Autodesk Fusion 360 part; units mm, degrees
(part 18 of 28)
  line L1257 (50.9078, 31.8439) -> (50.9969, 31.6692)
  line L1258 (50.9969, 31.6692) -> (51.0575, 31.4826)
  line L1259 (51.0575, 31.4826) -> (51.0882, 31.2889)
  line L1260 (51.0882, 31.2889) -> (51.092, 31.1908)
  line L1261 (51.092, 31.1908) -> (51.092, 30.6908)
  line L1262 (51.092, 30.6908) -> (51.0882, 30.5927)
  line L1263 (51.0882, 30.5927) -> (51.0575, 30.399)
  line L1264 (51.0575, 30.399) -> (50.9969, 30.2125)
  line L1265 (50.9969, 30.2125) -> (50.9078, 30.0377)
  line L1266 (50.9078, 30.0377) -> (50.7925, 29.879)
  line L1267 (50.7925, 29.879) -> (50.6538, 29.7403)
  line L1268 (50.6538, 29.7403) -> (50.4952, 29.625)
  line L1269 (50.4952, 29.625) -> (50.3204, 29.536)
  line L1270 (50.3204, 29.536) -> (50.1338, 29.4754)
  line L1271 (50.1338, 29.4754) -> (49.9401, 29.4447)
  line L1272 (49.9401, 29.4447) -> (49.744, 29.4447)
  line L1273 (49.744, 29.4447) -> (49.5502, 29.4754)
  line L1274 (49.5502, 29.4754) -> (49.3637, 29.536)
  line L1275 (49.3637, 29.536) -> (49.1889, 29.625)
  line L1276 (49.1889, 29.625) -> (49.0302, 29.7403)
  line L1277 (49.0302, 29.7403) -> (48.8915, 29.879)
  line L1278 (48.8915, 29.879) -> (48.7762, 30.0377)
  line L1279 (48.7762, 30.0377) -> (48.6872, 30.2125)
  line L1280 (48.6872, 30.2125) -> (48.6266, 30.399)
  line L1281 (48.6266, 30.399) -> (48.5959, 30.5927)
  line L1282 (48.5959, 30.5927) -> (48.592, 30.6908)
  line L1283 (48.592, 30.6908) -> (48.592, 31.1908)
  line L1284 (48.592, 31.1908) -> (48.5959, 31.2889)
  line L1285 (48.5959, 31.2889) -> (48.6266, 31.4826)
  line L1286 (48.6266, 31.4826) -> (48.6872, 31.6692)
  line L1287 (48.6872, 31.6692) -> (48.7762, 31.8439)
  line L1288 (48.7762, 31.8439) -> (48.8915, 32.0026)
  line L1289 (48.8915, 32.0026) -> (49.0302, 32.1413)
  line L1290 (49.0302, 32.1413) -> (49.1889, 32.2566)
  line L1291 (49.1889, 32.2566) -> (49.3637, 32.3457)
  line L1292 (49.3637, 32.3457) -> (49.5502, 32.4063)
  line L1293 (49.5502, 32.4063) -> (49.744, 32.437)
  line L1294 (49.744, 32.437) -> (49.9401, 32.437)
  line L1295 (49.9401, 32.437) -> (50.1338, 32.4063)
  line L1296 (111.0938, 32.4063) -> (111.2804, 32.3457)
  line L1297 (111.2804, 32.3457) -> (111.4552, 32.2566)
  line L1298 (111.4552, 32.2566) -> (111.6138, 32.1413)
  line L1299 (111.6138, 32.1413) -> (111.7525, 32.0026)
  line L1300 (111.7525, 32.0026) -> (111.8678, 31.8439)
  line L1301 (111.8678, 31.8439) -> (111.9569, 31.6692)
  line L1302 (111.9569, 31.6692) -> (112.0175, 31.4826)
  line L1303 (112.0175, 31.4826) -> (112.0482, 31.2889)
  line L1304 (112.0482, 31.2889) -> (112.052, 31.1908)
  line L1305 (112.052, 31.1908) -> (112.052, 30.6908)
  line L1306 (112.052, 30.6908) -> (112.0482, 30.5927)
  line L1307 (112.0482, 30.5927) -> (112.0175, 30.399)
  line L1308 (112.0175, 30.399) -> (111.9569, 30.2125)
  line L1309 (111.9569, 30.2125) -> (111.8678, 30.0377)
  line L1310 (111.8678, 30.0377) -> (111.7525, 29.879)
  line L1311 (111.7525, 29.879) -> (111.6138, 29.7403)
  line L1312 (111.6138, 29.7403) -> (111.4552, 29.625)
  line L1313 (111.4552, 29.625) -> (111.2804, 29.536)
  line L1314 (111.2804, 29.536) -> (111.0938, 29.4754)
  line L1315 (111.0938, 29.4754) -> (110.9001, 29.4447)
  line L1316 (110.9001, 29.4447) -> (110.704, 29.4447)
  line L1317 (110.704, 29.4447) -> (110.5102, 29.4754)
  line L1318 (110.5102, 29.4754) -> (110.3237, 29.536)
  line L1319 (110.3237, 29.536) -> (110.1489, 29.625)
  line L1320 (110.1489, 29.625) -> (109.9902, 29.7403)
  line L1321 (109.9902, 29.7403) -> (109.8515, 29.879)
  line L1322 (109.8515, 29.879) -> (109.7362, 30.0377)
  line L1323 (109.7362, 30.0377) -> (109.6472, 30.2125)
  line L1324 (109.6472, 30.2125) -> (109.5866, 30.399)
  line L1325 (109.5866, 30.399) -> (109.5559, 30.5927)
  line L1326 (109.5559, 30.5927) -> (109.552, 30.6908)
  line L1327 (109.552, 30.6908) -> (109.552, 31.1908)
  line L1328 (109.552, 31.1908) -> (109.5559, 31.2889)
  line L1329 (109.5559, 31.2889) -> (109.5866, 31.4826)
  line L1330 (109.5866, 31.4826) -> (109.6472, 31.6692)
  line L1331 (109.6472, 31.6692) -> (109.7362, 31.8439)
  line L1332 (109.7362, 31.8439) -> (109.8515, 32.0026)
  line L1333 (109.8515, 32.0026) -> (109.9902, 32.1413)
  line L1334 (109.9902, 32.1413) -> (110.1489, 32.2566)
  line L1335 (110.1489, 32.2566) -> (110.3237, 32.3457)
  line L1336 (110.3237, 32.3457) -> (110.5102, 32.4063)
  line L1337 (110.5102, 32.4063) -> (110.704, 32.437)
  line L1338 (110.704, 32.437) -> (110.9001, 32.437)
  line L1339 (110.9001, 32.437) -> (111.0938, 32.4063)
  line L1340 (23.2295, 32.6644) -> (23.3427, 32.6091)
  line L1341 (23.3427, 32.6091) -> (23.4319, 32.5199)
  line L1342 (23.4319, 32.5199) -> (23.4872, 32.4067)
  line L1343 (23.4872, 32.4067) -> (23.5031, 32.2975)
  line L1344 (23.5031, 32.2975) -> (23.5031, 30.6131)
  line L1345 (23.5031, 30.6131) -> (23.4872, 30.5039)
  line L1346 (23.4872, 30.5039) -> (23.4319, 30.3907)
  line L1347 (23.4319, 30.3907) -> (23.3427, 30.3016)
  line L1348 (23.3427, 30.3016) -> (23.2295, 30.2462)
  line L1349 (23.2295, 30.2462) -> (23.1203, 30.2303)
  line L1350 (23.1203, 30.2303) -> (20.8859, 30.2303)
  line L1351 (20.8859, 30.2303) -> (20.7767, 30.2462)
  line L1352 (20.7767, 30.2462) -> (20.6635, 30.3016)
  line L1353 (20.6635, 30.3016) -> (20.5744, 30.3907)
  line L1354 (20.5744, 30.3907) -> (20.519, 30.5039)
  line L1355 (20.519, 30.5039) -> (20.5031, 30.6131)
  line L1356 (20.5031, 30.6131) -> (20.5031, 32.2975)
  line L1357 (20.5031, 32.2975) -> (20.519, 32.4067)
  line L1358 (20.519, 32.4067) -> (20.5744, 32.5199)
  line L1359 (20.5744, 32.5199) -> (20.6635, 32.6091)
  line L1360 (20.6635, 32.6091) -> (20.7767, 32.6644)
  line L1361 (20.7767, 32.6644) -> (20.8859, 32.6803)
  line L1362 (20.8859, 32.6803) -> (23.1203, 32.6803)
  line L1363 (23.1203, 32.6803) -> (23.2295, 32.6644)
  line L1364 (84.1895, 32.6644) -> (84.3027, 32.6091)
  line L1365 (84.3027, 32.6091) -> (84.3919, 32.5199)
  line L1366 (84.3919, 32.5199) -> (84.4472, 32.4067)
  line L1367 (84.4472, 32.4067) -> (84.4631, 32.2975)
  line L1368 (84.4631, 32.2975) -> (84.4631, 30.6131)
  line L1369 (84.4631, 30.6131) -> (84.4472, 30.5039)
  line L1370 (84.4472, 30.5039) -> (84.3919, 30.3907)
  line L1371 (84.3919, 30.3907) -> (84.3027, 30.3016)
  line L1372 (84.3027, 30.3016) -> (84.1895, 30.2462)
  line L1373 (84.1895, 30.2462) -> (84.0803, 30.2303)
  line L1374 (84.0803, 30.2303) -> (81.8459, 30.2303)
  line L1375 (81.8459, 30.2303) -> (81.7367, 30.2462)
  line L1376 (81.7367, 30.2462) -> (81.6235, 30.3016)
  line L1377 (81.6235, 30.3016) -> (81.5344, 30.3907)
  line L1378 (81.5344, 30.3907) -> (81.479, 30.5039)
  line L1379 (81.479, 30.5039) -> (81.4631, 30.6131)
  line L1380 (81.4631, 30.6131) -> (81.4631, 32.2975)
  line L1381 (81.4631, 32.2975) -> (81.479, 32.4067)
  line L1382 (81.479, 32.4067) -> (81.5344, 32.5199)
  line L1383 (81.5344, 32.5199) -> (81.6235, 32.6091)
  line L1384 (81.6235, 32.6091) -> (81.7367, 32.6644)
  line L1385 (81.7367, 32.6644) -> (81.8459, 32.6803)
  line L1386 (81.8459, 32.6803) -> (84.0803, 32.6803)
  line L1387 (84.0803, 32.6803) -> (84.1895, 32.6644)
  line L1388 (10.9199, 32.7804) -> (11.1098, 32.7504)
  line L1389 (11.1098, 32.7504) -> (11.2926, 32.691)
  line L1390 (11.2926, 32.691) -> (11.4639, 32.6037)
  line L1391 (11.4639, 32.6037) -> (11.6194, 32.4907)
  line L1392 (11.6194, 32.4907) -> (11.7553, 32.3548)
  line L1393 (11.7553, 32.3548) -> (11.8683, 32.1993)
  line L1394 (11.8683, 32.1993) -> (11.9556, 32.028)
  line L1395 (11.9556, 32.028) -> (12.015, 31.8452)
  line L1396 (12.015, 31.8452) -> (12.0451, 31.6553)
  line L1397 (12.0451, 31.6553) -> (12.0451, 31.4631)
  line L1398 (12.0451, 31.4631) -> (12.015, 31.2732)
  line L1399 (12.015, 31.2732) -> (11.9556, 31.0904)
  line L1400 (11.9556, 31.0904) -> (11.8683, 30.9191)
  line L1401 (11.8683, 30.9191) -> (11.7553, 30.7636)
  line L1402 (11.7553, 30.7636) -> (11.6194, 30.6277)
  line L1403 (11.6194, 30.6277) -> (11.4639, 30.5147)
  line L1404 (11.4639, 30.5147) -> (11.2926, 30.4274)
  line L1405 (11.2926, 30.4274) -> (11.1098, 30.368)
  line L1406 (11.1098, 30.368) -> (10.9199, 30.338)
  line L1407 (10.9199, 30.338) -> (10.8238, 30.3342)
  line L1408 (10.8238, 30.3342) -> (10.2738, 30.3342)
  line L1409 (10.2738, 30.3342) -> (10.1777, 30.338)
  line L1410 (10.1777, 30.338) -> (9.9879, 30.368)
  line L1411 (9.9879, 30.368) -> (9.8051, 30.4274)
  line L1412 (9.8051, 30.4274) -> (9.6338, 30.5147)
  line L1413 (9.6338, 30.5147) -> (9.4783, 30.6277)
  line L1414 (9.4783, 30.6277) -> (9.3423, 30.7636)
  line L1415 (9.3423, 30.7636) -> (9.2294, 30.9191)
  line L1416 (9.2294, 30.9191) -> (9.1421, 31.0904)
  line L1417 (9.1421, 31.0904) -> (9.0827, 31.2732)
  line L1418 (9.0827, 31.2732) -> (9.0526, 31.4631)
  line L1419 (9.0526, 31.4631) -> (9.0526, 31.6553)
  line L1420 (9.0526, 31.6553) -> (9.0827, 31.8452)
  line L1421 (9.0827, 31.8452) -> (9.1421, 32.028)
  line L1422 (9.1421, 32.028) -> (9.2294, 32.1993)
  line L1423 (9.2294, 32.1993) -> (9.3423, 32.3548)
  line L1424 (9.3423, 32.3548) -> (9.4783, 32.4907)
  line L1425 (9.4783, 32.4907) -> (9.6338, 32.6037)
  line L1426 (9.6338, 32.6037) -> (9.8051, 32.691)
  line L1427 (9.8051, 32.691) -> (9.9879, 32.7504)
  line L1428 (9.9879, 32.7504) -> (10.1777, 32.7804)
  line L1429 (10.1777, 32.7804) -> (10.2738, 32.7842)
  line L1430 (10.2738, 32.7842) -> (10.8238, 32.7842)
  line L1431 (10.8238, 32.7842) -> (10.9199, 32.7804)
  line L1432 (71.8799, 32.7804) -> (72.0698, 32.7504)
  line L1433 (72.0698, 32.7504) -> (72.2526, 32.691)
  line L1434 (72.2526, 32.691) -> (72.4239, 32.6037)
  line L1435 (72.4239, 32.6037) -> (72.5794, 32.4907)
  line L1436 (72.5794, 32.4907) -> (72.7153, 32.3548)
  line L1437 (72.7153, 32.3548) -> (72.8283, 32.1993)
  line L1438 (72.8283, 32.1993) -> (72.9156, 32.028)
  line L1439 (72.9156, 32.028) -> (72.975, 31.8452)
  line L1440 (72.975, 31.8452) -> (73.0051, 31.6553)
  line L1441 (73.0051, 31.6553) -> (73.0051, 31.4631)
  line L1442 (73.0051, 31.4631) -> (72.975, 31.2732)
  line L1443 (72.975, 31.2732) -> (72.9156, 31.0904)
  line L1444 (72.9156, 31.0904) -> (72.8283, 30.9191)
  line L1445 (72.8283, 30.9191) -> (72.7153, 30.7636)
  line L1446 (72.7153, 30.7636) -> (72.5794, 30.6277)
  line L1447 (72.5794, 30.6277) -> (72.4239, 30.5147)
  line L1448 (72.4239, 30.5147) -> (72.2526, 30.4274)
  line L1449 (72.2526, 30.4274) -> (72.0698, 30.368)
  line L1450 (72.0698, 30.368) -> (71.8799, 30.338)
  line L1451 (71.8799, 30.338) -> (71.7838, 30.3342)
  line L1452 (71.7838, 30.3342) -> (71.2338, 30.3342)
  line L1453 (71.2338, 30.3342) -> (71.1377, 30.338)
  line L1454 (71.1377, 30.338) -> (70.9479, 30.368)
  line L1455 (70.9479, 30.368) -> (70.7651, 30.4274)
  line L1456 (70.7651, 30.4274) -> (70.5938, 30.5147)
  line L1457 (70.5938, 30.5147) -> (70.4383, 30.6277)
  line L1458 (70.4383, 30.6277) -> (70.3023, 30.7636)
  line L1459 (70.3023, 30.7636) -> (70.1894, 30.9191)
  line L1460 (70.1894, 30.9191) -> (70.1021, 31.0904)
  line L1461 (70.1021, 31.0904) -> (70.0427, 31.2732)
  line L1462 (70.0427, 31.2732) -> (70.0126, 31.4631)
  line L1463 (70.0126, 31.4631) -> (70.0126, 31.6553)
  line L1464 (70.0126, 31.6553) -> (70.0427, 31.8452)
  line L1465 (70.0427, 31.8452) -> (70.1021, 32.028)
  line L1466 (70.1021, 32.028) -> (70.1894, 32.1993)
  line L1467 (70.1894, 32.1993) -> (70.3023, 32.3548)
  line L1468 (70.3023, 32.3548) -> (70.4383, 32.4907)
  line L1469 (70.4383, 32.4907) -> (70.5938, 32.6037)
  line L1470 (70.5938, 32.6037) -> (70.7651, 32.691)
  line L1471 (70.7651, 32.691) -> (70.9479, 32.7504)
  line L1472 (70.9479, 32.7504) -> (71.1377, 32.7804)
  line L1473 (71.1377, 32.7804) -> (71.2338, 32.7842)
  line L1474 (71.2338, 32.7842) -> (71.7838, 32.7842)
  line L1475 (71.7838, 32.7842) -> (71.8799, 32.7804)
  line L1476 (44.7485, 30.6785) -> (41.5485, 30.6785)
  line L1477 (41.5485, 30.6785) -> (41.5485, 32.6785)
  line L1478 (41.5485, 32.6785) -> (44.7485, 32.6785)
  line L1479 (44.7485, 32.6785) -> (44.7485, 30.6785)
  line L1480 (105.7085, 30.6785) -> (102.5085, 30.6785)
  line L1481 (102.5085, 30.6785) -> (102.5085, 32.6785)
  line L1482 (102.5085, 32.6785) -> (105.7085, 32.6785)
  line L1483 (105.7085, 32.6785) -> (105.7085, 30.6785)
  line L1484 (17.2908, 40.7988) -> (14.8408, 40.7988)
  line L1485 (14.8408, 40.7988) -> (14.8408, 43.7988)
  line L1486 (14.8408, 43.7988) -> (17.2908, 43.7988)
  line L1487 (17.2908, 43.7988) -> (17.2908, 40.7988)
  line L1488 (52.2158, 40.7988) -> (49.7658, 40.7988)
  line L1489 (49.7658, 40.7988) -> (49.7658, 43.7988)
  line L1490 (49.7658, 43.7988) -> (52.2158, 43.7988)
  line L1491 (52.2158, 43.7988) -> (52.2158, 40.7988)
  line L1492 (87.1408, 40.7988) -> (84.6908, 40.7988)
  line L1493 (84.6908, 40.7988) -> (84.6908, 43.7988)
  line L1494 (84.6908, 43.7988) -> (87.1408, 43.7988)
  line L1495 (87.1408, 43.7988) -> (87.1408, 40.7988)
  line L1496 (122.0658, 40.7988) -> (119.6158, 40.7988)
  line L1497 (119.6158, 40.7988) -> (119.6158, 43.7988)
  line L1498 (119.6158, 43.7988) -> (122.0658, 43.7988)
  line L1499 (122.0658, 43.7988) -> (122.0658, 40.7988)
  line L1500 (13.8118, 43.765) -> (13.9946, 43.7056)
  line L1501 (13.9946, 43.7056) -> (14.1659, 43.6183)
  line L1502 (14.1659, 43.6183) -> (14.3214, 43.5053)
  line L1503 (14.3214, 43.5053) -> (14.4573, 43.3694)
  line L1504 (14.4573, 43.3694) -> (14.5703, 43.2139)
  line L1505 (14.5703, 43.2139) -> (14.6576, 43.0426)
  line L1506 (14.6576, 43.0426) -> (14.717, 42.8598)
  line L1507 (14.717, 42.8598) -> (14.747, 42.6699)
  line L1508 (14.747, 42.6699) -> (14.7508, 42.5738)
  line L1509 (14.7508, 42.5738) -> (14.7508, 42.0238)
  line L1510 (14.7508, 42.0238) -> (14.747, 41.9277)
  line L1511 (14.747, 41.9277) -> (14.717, 41.7379)
  line L1512 (14.717, 41.7379) -> (14.6576, 41.555)
  line L1513 (14.6576, 41.555) -> (14.5703, 41.3838)
  line L1514 (14.5703, 41.3838) -> (14.4573, 41.2283)
  line L1515 (14.4573, 41.2283) -> (14.3214, 41.0923)
  line L1516 (14.3214, 41.0923) -> (14.1659, 40.9794)
  line L1517 (14.1659, 40.9794) -> (13.9946, 40.8921)
  line L1518 (13.9946, 40.8921) -> (13.8118, 40.8327)
  line L1519 (13.8118, 40.8327) -> (13.6219, 40.8026)
  line L1520 (13.6219, 40.8026) -> (13.4297, 40.8026)
  line L1521 (13.4297, 40.8026) -> (13.2398, 40.8327)
  line L1522 (13.2398, 40.8327) -> (13.057, 40.8921)
  line L1523 (13.057, 40.8921) -> (12.8857, 40.9794)
  line L1524 (12.8857, 40.9794) -> (12.7302, 41.0923)
  line L1525 (12.7302, 41.0923) -> (12.5943, 41.2283)
  line L1526 (12.5943, 41.2283) -> (12.4813, 41.3838)
  line L1527 (12.4813, 41.3838) -> (12.394, 41.5551)
  line L1528 (12.394, 41.5551) -> (12.3346, 41.7379)
  line L1529 (12.3346, 41.7379) -> (12.3046, 41.9277)
  line L1530 (12.3046, 41.9277) -> (12.3008, 42.0238)
  line L1531 (12.3008, 42.0238) -> (12.3008, 42.5738)
  line L1532 (12.3008, 42.5738) -> (12.3046, 42.6699)
  line L1533 (12.3046, 42.6699) -> (12.3346, 42.8598)
  line L1534 (12.3346, 42.8598) -> (12.394, 43.0426)
  line L1535 (12.394, 43.0426) -> (12.4813, 43.2139)
  line L1536 (12.4813, 43.2139) -> (12.5943, 43.3694)
  line L1537 (12.5943, 43.3694) -> (12.7302, 43.5053)
  line L1538 (12.7302, 43.5053) -> (12.8857, 43.6183)
  line L1539 (12.8857, 43.6183) -> (13.057, 43.7056)
  line L1540 (13.057, 43.7056) -> (13.2398, 43.765)
  line L1541 (13.2398, 43.765) -> (13.4297, 43.7951)
  line L1542 (13.4297, 43.7951) -> (13.6219, 43.7951)
  line L1543 (13.6219, 43.7951) -> (13.8118, 43.765)
  line L1544 (48.7368, 43.765) -> (48.9196, 43.7056)
  line L1545 (48.9196, 43.7056) -> (49.0909, 43.6183)
  line L1546 (49.0909, 43.6183) -> (49.2464, 43.5053)
  line L1547 (49.2464, 43.5053) -> (49.3823, 43.3694)
  line L1548 (49.3823, 43.3694) -> (49.4953, 43.2139)
  line L1549 (49.4953, 43.2139) -> (49.5826, 43.0426)
  line L1550 (49.5826, 43.0426) -> (49.642, 42.8598)
  line L1551 (49.642, 42.8598) -> (49.672, 42.6699)
  line L1552 (49.672, 42.6699) -> (49.6758, 42.5738)
  line L1553 (49.6758, 42.5738) -> (49.6758, 42.0238)
  line L1554 (49.6758, 42.0238) -> (49.672, 41.9277)
  line L1555 (49.672, 41.9277) -> (49.642, 41.7379)
  line L1556 (49.642, 41.7379) -> (49.5826, 41.555)
  line L1557 (49.5826, 41.555) -> (49.4953, 41.3838)
  line L1558 (49.4953, 41.3838) -> (49.3823, 41.2283)
  line L1559 (49.3823, 41.2283) -> (49.2464, 41.0923)
  line L1560 (49.2464, 41.0923) -> (49.0909, 40.9794)
  line L1561 (49.0909, 40.9794) -> (48.9196, 40.8921)
  line L1562 (48.9196, 40.8921) -> (48.7368, 40.8327)
  line L1563 (48.7368, 40.8327) -> (48.5469, 40.8026)
  line L1564 (48.5469, 40.8026) -> (48.3547, 40.8026)
  line L1565 (48.3547, 40.8026) -> (48.1648, 40.8327)
  line L1566 (48.1648, 40.8327) -> (47.982, 40.8921)
  line L1567 (47.982, 40.8921) -> (47.8107, 40.9794)
  line L1568 (47.8107, 40.9794) -> (47.6552, 41.0923)
  line L1569 (47.6552, 41.0923) -> (47.5193, 41.2283)
  line L1570 (47.5193, 41.2283) -> (47.4063, 41.3838)
  line L1571 (47.4063, 41.3838) -> (47.319, 41.5551)
  line L1572 (47.319, 41.5551) -> (47.2596, 41.7379)
  line L1573 (47.2596, 41.7379) -> (47.2296, 41.9277)
  line L1574 (47.2296, 41.9277) -> (47.2258, 42.0238)
  line L1575 (47.2258, 42.0238) -> (47.2258, 42.5738)
  line L1576 (47.2258, 42.5738) -> (47.2296, 42.6699)
  line L1577 (47.2296, 42.6699) -> (47.2596, 42.8598)
  line L1578 (47.2596, 42.8598) -> (47.319, 43.0426)
  line L1579 (47.319, 43.0426) -> (47.4063, 43.2139)
  line L1580 (47.4063, 43.2139) -> (47.5193, 43.3694)
  line L1581 (47.5193, 43.3694) -> (47.6552, 43.5053)
  line L1582 (47.6552, 43.5053) -> (47.8107, 43.6183)
  line L1583 (47.8107, 43.6183) -> (47.982, 43.7056)
  line L1584 (47.982, 43.7056) -> (48.1648, 43.765)
  line L1585 (48.1648, 43.765) -> (48.3547, 43.7951)
  line L1586 (48.3547, 43.7951) -> (48.5469, 43.7951)
  line L1587 (48.5469, 43.7951) -> (48.7368, 43.765)
  line L1588 (83.6618, 43.765) -> (83.8446, 43.7056)
  line L1589 (83.8446, 43.7056) -> (84.0159, 43.6183)
  line L1590 (84.0159, 43.6183) -> (84.1714, 43.5053)
  line L1591 (84.1714, 43.5053) -> (84.3073, 43.3694)
  line L1592 (84.3073, 43.3694) -> (84.4203, 43.2139)
  line L1593 (84.4203, 43.2139) -> (84.5076, 43.0426)
  line L1594 (84.5076, 43.0426) -> (84.567, 42.8598)
  line L1595 (84.567, 42.8598) -> (84.597, 42.6699)
  line L1596 (84.597, 42.6699) -> (84.6008, 42.5738)
  line L1597 (84.6008, 42.5738) -> (84.6008, 42.0238)
  line L1598 (84.6008, 42.0238) -> (84.597, 41.9277)
  line L1599 (84.597, 41.9277) -> (84.567, 41.7379)
  line L1600 (84.567, 41.7379) -> (84.5076, 41.555)
  line L1601 (84.5076, 41.555) -> (84.4203, 41.3838)
  line L1602 (84.4203, 41.3838) -> (84.3073, 41.2283)
  line L1603 (84.3073, 41.2283) -> (84.1714, 41.0923)
  line L1604 (84.1714, 41.0923) -> (84.0159, 40.9794)
  line L1605 (84.0159, 40.9794) -> (83.8446, 40.8921)
  line L1606 (83.8446, 40.8921) -> (83.6618, 40.8327)
  line L1607 (83.6618, 40.8327) -> (83.4719, 40.8026)
  line L1608 (83.4719, 40.8026) -> (83.2797, 40.8026)
  line L1609 (83.2797, 40.8026) -> (83.0898, 40.8327)
  line L1610 (83.0898, 40.8327) -> (82.907, 40.8921)
  line L1611 (82.907, 40.8921) -> (82.7357, 40.9794)
  line L1612 (82.7357, 40.9794) -> (82.5802, 41.0923)
  line L1613 (82.5802, 41.0923) -> (82.4443, 41.2283)
  line L1614 (82.4443, 41.2283) -> (82.3313, 41.3838)
  line L1615 (82.3313, 41.3838) -> (82.244, 41.5551)
  line L1616 (82.244, 41.5551) -> (82.1846, 41.7379)
  line L1617 (82.1846, 41.7379) -> (82.1546, 41.9277)
  line L1618 (82.1546, 41.9277) -> (82.1508, 42.0238)
  line L1619 (82.1508, 42.0238) -> (82.1508, 42.5738)
  line L1620 (82.1508, 42.5738) -> (82.1546, 42.6699)
  line L1621 (82.1546, 42.6699) -> (82.1846, 42.8598)
  line L1622 (82.1846, 42.8598) -> (82.244, 43.0426)
  line L1623 (82.244, 43.0426) -> (82.3313, 43.2139)
  line L1624 (82.3313, 43.2139) -> (82.4443, 43.3694)
  line L1625 (82.4443, 43.3694) -> (82.5802, 43.5053)
  line L1626 (82.5802, 43.5053) -> (82.7357, 43.6183)
  line L1627 (82.7357, 43.6183) -> (82.907, 43.7056)
  line L1628 (82.907, 43.7056) -> (83.0898, 43.765)
  line L1629 (83.0898, 43.765) -> (83.2797, 43.7951)
  line L1630 (83.2797, 43.7951) -> (83.4719, 43.7951)
  line L1631 (83.4719, 43.7951) -> (83.6618, 43.765)
  line L1632 (118.5868, 43.765) -> (118.7696, 43.7056)
  line L1633 (118.7696, 43.7056) -> (118.9409, 43.6183)
  line L1634 (118.9409, 43.6183) -> (119.0964, 43.5053)
  line L1635 (119.0964, 43.5053) -> (119.2323, 43.3694)
  line L1636 (119.2323, 43.3694) -> (119.3453, 43.2139)
  line L1637 (119.3453, 43.2139) -> (119.4326, 43.0426)
  line L1638 (119.4326, 43.0426) -> (119.492, 42.8598)
  line L1639 (119.492, 42.8598) -> (119.522, 42.6699)
  line L1640 (119.522, 42.6699) -> (119.5258, 42.5738)
  line L1641 (119.5258, 42.5738) -> (119.5258, 42.0238)
  line L1642 (119.5258, 42.0238) -> (119.522, 41.9277)
  line L1643 (119.522, 41.9277) -> (119.492, 41.7379)
  line L1644 (119.492, 41.7379) -> (119.4326, 41.555)
  line L1645 (119.4326, 41.555) -> (119.3453, 41.3838)
  line L1646 (119.3453, 41.3838) -> (119.2323, 41.2283)
  line L1647 (119.2323, 41.2283) -> (119.0964, 41.0923)
  line L1648 (119.0964, 41.0923) -> (118.9409, 40.9794)
  line L1649 (118.9409, 40.9794) -> (118.7696, 40.8921)
  line L1650 (118.7696, 40.8921) -> (118.5868, 40.8327)
  line L1651 (118.5868, 40.8327) -> (118.3969, 40.8026)
  line L1652 (118.3969, 40.8026) -> (118.2047, 40.8026)
  line L1653 (118.2047, 40.8026) -> (118.0148, 40.8327)
  line L1654 (118.0148, 40.8327) -> (117.832, 40.8921)
  line L1655 (117.832, 40.8921) -> (117.6607, 40.9794)
  line L1656 (117.6607, 40.9794) -> (117.5052, 41.0923)
  line L1657 (117.5052, 41.0923) -> (117.3693, 41.2283)
  line L1658 (117.3693, 41.2283) -> (117.2563, 41.3838)
  line L1659 (117.2563, 41.3838) -> (117.169, 41.5551)
  line L1660 (117.169, 41.5551) -> (117.1096, 41.7379)
  line L1661 (117.1096, 41.7379) -> (117.0796, 41.9277)
  line L1662 (117.0796, 41.9277) -> (117.0758, 42.0238)
  line L1663 (117.0758, 42.0238) -> (117.0758, 42.5738)
  line L1664 (117.0758, 42.5738) -> (117.0796, 42.6699)
  line L1665 (117.0796, 42.6699) -> (117.1096, 42.8598)
  line L1666 (117.1096, 42.8598) -> (117.169, 43.0426)
  line L1667 (117.169, 43.0426) -> (117.2563, 43.2139)
  line L1668 (117.2563, 43.2139) -> (117.3693, 43.3694)
  line L1669 (117.3693, 43.3694) -> (117.5052, 43.5053)
  line L1670 (117.5052, 43.5053) -> (117.6607, 43.6183)
  line L1671 (117.6607, 43.6183) -> (117.832, 43.7056)
  line L1672 (117.832, 43.7056) -> (118.0148, 43.765)
  line L1673 (118.0148, 43.765) -> (118.2047, 43.7951)
  line L1674 (118.2047, 43.7951) -> (118.3969, 43.7951)
  line L1675 (118.3969, 43.7951) -> (118.5868, 43.765)
  line L1676 (25.7564, 54.8241) -> (25.8696, 54.7687)
  line L1677 (25.8696, 54.7687) -> (25.9587, 54.6796)
  line L1678 (25.9587, 54.6796) -> (26.0141, 54.5664)
  line L1679 (26.0141, 54.5664) -> (26.03, 54.4572)
  line L1680 (26.03, 54.4572) -> (26.03, 52.2228)
  line L1681 (26.03, 52.2228) -> (26.0141, 52.1136)
  line L1682 (26.0141, 52.1136) -> (25.9587, 52.0004)
  line L1683 (25.9587, 52.0004) -> (25.8696, 51.9113)
  line L1684 (25.8696, 51.9113) -> (25.7564, 51.8559)
  line L1685 (25.7564, 51.8559) -> (25.6472, 51.84)
  line L1686 (25.6472, 51.84) -> (23.9628, 51.84)
  line L1687 (23.9628, 51.84) -> (23.8536, 51.8559)
  line L1688 (23.8536, 51.8559) -> (23.7404, 51.9113)
  line L1689 (23.7404, 51.9113) -> (23.6513, 52.0004)
  line L1690 (23.6513, 52.0004) -> (23.5959, 52.1136)
  line L1691 (23.5959, 52.1136) -> (23.58, 52.2228)
  line L1692 (23.58, 52.2228) -> (23.58, 54.4572)
  line L1693 (23.58, 54.4572) -> (23.5959, 54.5664)
  line L1694 (23.5959, 54.5664) -> (23.6513, 54.6796)
  line L1695 (23.6513, 54.6796) -> (23.7404, 54.7687)
  line L1696 (23.7404, 54.7687) -> (23.8536, 54.8241)
  line L1697 (23.8536, 54.8241) -> (23.9628, 54.84)
  line L1698 (23.9628, 54.84) -> (25.6472, 54.84)
  line L1699 (25.6472, 54.84) -> (25.7564, 54.8241)
  line L1700 (60.6814, 54.8241) -> (60.7946, 54.7687)
  line L1701 (60.7946, 54.7687) -> (60.8837, 54.6796)
  line L1702 (60.8837, 54.6796) -> (60.9391, 54.5664)
  line L1703 (60.9391, 54.5664) -> (60.955, 54.4572)
  line L1704 (60.955, 54.4572) -> (60.955, 52.2228)
  line L1705 (60.955, 52.2228) -> (60.9391, 52.1136)
  line L1706 (60.9391, 52.1136) -> (60.8837, 52.0004)
  line L1707 (60.8837, 52.0004) -> (60.7946, 51.9113)
  line L1708 (60.7946, 51.9113) -> (60.6814, 51.8559)
  line L1709 (60.6814, 51.8559) -> (60.5722, 51.84)
  line L1710 (60.5722, 51.84) -> (58.8878, 51.84)
  line L1711 (58.8878, 51.84) -> (58.7786, 51.8559)
  line L1712 (58.7786, 51.8559) -> (58.6654, 51.9113)
  line L1713 (58.6654, 51.9113) -> (58.5763, 52.0004)
  line L1714 (58.5763, 52.0004) -> (58.5209, 52.1136)
  line L1715 (58.5209, 52.1136) -> (58.505, 52.2228)
  line L1716 (58.505, 52.2228) -> (58.505, 54.4572)
  line L1717 (58.505, 54.4572) -> (58.5209, 54.5664)
  line L1718 (58.5209, 54.5664) -> (58.5763, 54.6796)
  line L1719 (58.5763, 54.6796) -> (58.6654, 54.7687)
  line L1720 (58.6654, 54.7687) -> (58.7786, 54.8241)
  line L1721 (58.7786, 54.8241) -> (58.8878, 54.84)
  line L1722 (58.8878, 54.84) -> (60.5722, 54.84)
  line L1723 (60.5722, 54.84) -> (60.6814, 54.8241)
  line L1724 (95.6064, 54.8241) -> (95.7196, 54.7687)
  line L1725 (95.7196, 54.7687) -> (95.8087, 54.6796)
  line L1726 (95.8087, 54.6796) -> (95.8641, 54.5664)
  line L1727 (95.8641, 54.5664) -> (95.88, 54.4572)
  line L1728 (95.88, 54.4572) -> (95.88, 52.2228)
  line L1729 (95.88, 52.2228) -> (95.8641, 52.1136)
  line L1730 (95.8641, 52.1136) -> (95.8087, 52.0004)
  line L1731 (95.8087, 52.0004) -> (95.7196, 51.9113)
  line L1732 (95.7196, 51.9113) -> (95.6064, 51.8559)
  line L1733 (95.6064, 51.8559) -> (95.4972, 51.84)
  line L1734 (95.4972, 51.84) -> (93.8128, 51.84)
  line L1735 (93.8128, 51.84) -> (93.7036, 51.8559)
  line L1736 (93.7036, 51.8559) -> (93.5904, 51.9113)
  line L1737 (93.5904, 51.9113) -> (93.5013, 52.0004)
  line L1738 (93.5013, 52.0004) -> (93.4459, 52.1136)
  line L1739 (93.4459, 52.1136) -> (93.43, 52.2228)
  line L1740 (93.43, 52.2228) -> (93.43, 54.4572)
  line L1741 (93.43, 54.4572) -> (93.4459, 54.5664)
  line L1742 (93.4459, 54.5664) -> (93.5013, 54.6796)
  line L1743 (93.5013, 54.6796) -> (93.5904, 54.7687)
  line L1744 (93.5904, 54.7687) -> (93.7036, 54.8241)
  line L1745 (93.7036, 54.8241) -> (93.8128, 54.84)
  line L1746 (93.8128, 54.84) -> (95.4972, 54.84)
  line L1747 (95.4972, 54.84) -> (95.6064, 54.8241)
  line L1748 (130.5314, 54.8241) -> (130.6446, 54.7687)
  line L1749 (130.6446, 54.7687) -> (130.7337, 54.6796)
  line L1750 (130.7337, 54.6796) -> (130.7891, 54.5664)
  line L1751 (130.7891, 54.5664) -> (130.805, 54.4572)
  line L1752 (130.805, 54.4572) -> (130.805, 52.2228)
  line L1753 (130.805, 52.2228) -> (130.7891, 52.1136)
  line L1754 (130.7891, 52.1136) -> (130.7337, 52.0004)
  line L1755 (130.7337, 52.0004) -> (130.6446, 51.9113)
  line L1756 (130.6446, 51.9113) -> (130.5314, 51.8559)
  line L1757 (130.5314, 51.8559) -> (130.4222, 51.84)
  line L1758 (130.4222, 51.84) -> (128.7378, 51.84)
  line L1759 (128.7378, 51.84) -> (128.6286, 51.8559)
  line L1760 (128.6286, 51.8559) -> (128.5154, 51.9113)
  line L1761 (128.5154, 51.9113) -> (128.4263, 52.0004)
  line L1762 (128.4263, 52.0004) -> (128.3709, 52.1136)
  line L1763 (128.3709, 52.1136) -> (128.355, 52.2228)
  line L1764 (128.355, 52.2228) -> (128.355, 54.4572)
  line L1765 (128.355, 54.4572) -> (128.3709, 54.5664)
  line L1766 (128.3709, 54.5664) -> (128.4263, 54.6796)
  line L1767 (128.4263, 54.6796) -> (128.5154, 54.7687)
  line L1768 (128.5154, 54.7687) -> (128.6286, 54.8241)
  line L1769 (128.6286, 54.8241) -> (128.7378, 54.84)
  line L1770 (128.7378, 54.84) -> (130.4222, 54.84)
  line L1771 (130.4222, 54.84) -> (130.5314, 54.8241)
  line L1772 (27.591, 54.8062) -> (27.7738, 54.7468)
  line L1773 (27.7738, 54.7468) -> (27.9451, 54.6595)
  line L1774 (27.9451, 54.6595) -> (28.1006, 54.5465)
  line L1775 (28.1006, 54.5465) -> (28.2365, 54.4106)
  line L1776 (28.2365, 54.4106) -> (28.3495, 54.2551)
  line L1777 (28.3495, 54.2551) -> (28.4368, 54.0838)
  line L1778 (28.4368, 54.0838) -> (28.4962, 53.901)
  line L1779 (28.4962, 53.901) -> (28.5262, 53.7111)
  line L1780 (28.5262, 53.7111) -> (28.53, 53.615)
  line L1781 (28.53, 53.615) -> (28.53, 53.065)
  line L1782 (28.53, 53.065) -> (28.5262, 52.9689)
  line L1783 (28.5262, 52.9689) -> (28.4962, 52.779)
  line L1784 (28.4962, 52.779) -> (28.4368, 52.5962)
  line L1785 (28.4368, 52.5962) -> (28.3495, 52.4249)
  line L1786 (28.3495, 52.4249) -> (28.2365, 52.2694)
  line L1787 (28.2365, 52.2694) -> (28.1006, 52.1335)
  line L1788 (28.1006, 52.1335) -> (27.9451, 52.0205)
  line L1789 (27.9451, 52.0205) -> (27.7738, 51.9332)
  line L1790 (27.7738, 51.9332) -> (27.591, 51.8738)
  line L1791 (27.591, 51.8738) -> (27.4011, 51.8438)
  line L1792 (27.4011, 51.8438) -> (27.2089, 51.8438)
  line L1793 (27.2089, 51.8438) -> (27.019, 51.8738)
  line L1794 (27.019, 51.8738) -> (26.8362, 51.9332)
  line L1795 (26.8362, 51.9332) -> (26.6649, 52.0205)
  line L1796 (26.6649, 52.0205) -> (26.5094, 52.1335)
  line L1797 (26.5094, 52.1335) -> (26.3735, 52.2694)
  line L1798 (26.3735, 52.2694) -> (26.2605, 52.4249)
  line L1799 (26.2605, 52.4249) -> (26.1732, 52.5962)
  line L1800 (26.1732, 52.5962) -> (26.1138, 52.779)
  line L1801 (26.1138, 52.779) -> (26.0838, 52.9689)
  line L1802 (26.0838, 52.9689) -> (26.08, 53.065)
  line L1803 (26.08, 53.065) -> (26.08, 53.615)
  line L1804 (26.08, 53.615) -> (26.0838, 53.7111)
  line L1805 (26.0838, 53.7111) -> (26.1138, 53.901)
  line L1806 (26.1138, 53.901) -> (26.1732, 54.0838)
  line L1807 (26.1732, 54.0838) -> (26.2605, 54.2551)
  line L1808 (26.2605, 54.2551) -> (26.3735, 54.4106)
  line L1809 (26.3735, 54.4106) -> (26.5094, 54.5465)
  line L1810 (26.5094, 54.5465) -> (26.6649, 54.6595)
  line L1811 (26.6649, 54.6595) -> (26.8362, 54.7468)
  line L1812 (26.8362, 54.7468) -> (27.019, 54.8062)
  line L1813 (27.019, 54.8062) -> (27.2089, 54.8362)
  line L1814 (27.2089, 54.8362) -> (27.4011, 54.8362)
  line L1815 (27.4011, 54.8362) -> (27.591, 54.8062)
  line L1816 (62.516, 54.8062) -> (62.6988, 54.7468)
  line L1817 (62.6988, 54.7468) -> (62.8701, 54.6595)
  line L1818 (62.8701, 54.6595) -> (63.0256, 54.5465)
  line L1819 (63.0256, 54.5465) -> (63.1615, 54.4106)
  line L1820 (63.1615, 54.4106) -> (63.2745, 54.2551)
  line L1821 (63.2745, 54.2551) -> (63.3618, 54.0838)
  line L1822 (63.3618, 54.0838) -> (63.4114, 53.9311)
  line L1823 (63.4114, 53.9311) -> (63.5485, 53.8943)
  line L1824 (63.5485, 53.8943) -> (63.6841, 53.816)
  line L1825 (63.6841, 53.816) -> (63.7949, 53.7053)
  line L1826 (63.7949, 53.7053) -> (63.8732, 53.5696)
  line L1827 (63.8732, 53.5696) -> (63.9137, 53.4183)
  line L1828 (63.9137, 53.4183) -> (63.9137, 53.2617)
  line L1829 (63.9137, 53.2617) -> (63.8732, 53.1104)
  line L1830 (63.8732, 53.1104) -> (63.7949, 52.9747)
  line L1831 (63.7949, 52.9747) -> (63.6841, 52.864)
  line L1832 (63.6841, 52.864) -> (63.5485, 52.7857)
  line L1833 (63.5485, 52.7857) -> (63.4114, 52.7489)
  line L1834 (63.4114, 52.7489) -> (63.3618, 52.5962)
  line L1835 (63.3618, 52.5962) -> (63.2745, 52.4249)
  line L1836 (63.2745, 52.4249) -> (63.1615, 52.2694)
  line L1837 (63.1615, 52.2694) -> (63.0256, 52.1335)
  line L1838 (63.0256, 52.1335) -> (62.8701, 52.0205)
  line L1839 (62.8701, 52.0205) -> (62.6988, 51.9332)
  line L1840 (62.6988, 51.9332) -> (62.516, 51.8738)
  line L1841 (62.516, 51.8738) -> (62.3261, 51.8438)
  line L1842 (62.3261, 51.8438) -> (62.1339, 51.8438)
  line L1843 (62.1339, 51.8438) -> (61.944, 51.8738)
  line L1844 (61.944, 51.8738) -> (61.7612, 51.9332)
  line L1845 (61.7612, 51.9332) -> (61.5899, 52.0205)
  line L1846 (61.5899, 52.0205) -> (61.4344, 52.1335)
  line L1847 (61.4344, 52.1335) -> (61.2985, 52.2694)
  line L1848 (61.2985, 52.2694) -> (61.1855, 52.4249)
  line L1849 (61.1855, 52.4249) -> (61.0982, 52.5962)
  line L1850 (61.0982, 52.5962) -> (61.0388, 52.779)
  line L1851 (61.0388, 52.779) -> (61.0088, 52.9689)
  line L1852 (61.0088, 52.9689) -> (61.005, 53.065)
  line L1853 (61.005, 53.065) -> (61.005, 53.615)
  line L1854 (61.005, 53.615) -> (61.0088, 53.7111)
  line L1855 (61.0088, 53.7111) -> (61.0388, 53.901)
  line L1856 (61.0388, 53.901) -> (61.0982, 54.0838)
  line L1857 (61.0982, 54.0838) -> (61.1855, 54.2551)
  line L1858 (61.1855, 54.2551) -> (61.2985, 54.4106)
  line L1859 (61.2985, 54.4106) -> (61.4344, 54.5465)
  line L1860 (61.4344, 54.5465) -> (61.5899, 54.6595)
  line L1861 (61.5899, 54.6595) -> (61.7612, 54.7468)
  line L1862 (61.7612, 54.7468) -> (61.944, 54.8062)
  line L1863 (61.944, 54.8062) -> (62.1339, 54.8362)
  line L1864 (62.1339, 54.8362) -> (62.3261, 54.8362)
  line L1865 (62.3261, 54.8362) -> (62.516, 54.8062)
  line L1866 (97.441, 54.8062) -> (97.6238, 54.7468)
  line L1867 (97.6238, 54.7468) -> (97.7951, 54.6595)
  line L1868 (97.7951, 54.6595) -> (97.9506, 54.5465)
  line L1869 (97.9506, 54.5465) -> (98.0865, 54.4106)
  line L1870 (98.0865, 54.4106) -> (98.1995, 54.2551)
  line L1871 (98.1995, 54.2551) -> (98.2868, 54.0838)
  line L1872 (98.2868, 54.0838) -> (98.3462, 53.901)
  line L1873 (98.3462, 53.901) -> (98.3762, 53.7111)
  line L1874 (98.3762, 53.7111) -> (98.38, 53.615)
  line L1875 (98.38, 53.615) -> (98.38, 53.065)
  line L1876 (98.38, 53.065) -> (98.3762, 52.9689)
  line L1877 (98.3762, 52.9689) -> (98.3462, 52.779)
  line L1878 (98.3462, 52.779) -> (98.2868, 52.5962)
  line L1879 (98.2868, 52.5962) -> (98.1995, 52.4249)
  line L1880 (98.1995, 52.4249) -> (98.0865, 52.2694)
  line L1881 (98.0865, 52.2694) -> (97.9506, 52.1335)
  line L1882 (97.9506, 52.1335) -> (97.7951, 52.0205)
  line L1883 (97.7951, 52.0205) -> (97.6238, 51.9332)
  line L1884 (97.6238, 51.9332) -> (97.441, 51.8738)
  line L1885 (97.441, 51.8738) -> (97.2511, 51.8438)
  line L1886 (97.2511, 51.8438) -> (97.0589, 51.8438)
  line L1887 (97.0589, 51.8438) -> (96.869, 51.8738)
  line L1888 (96.869, 51.8738) -> (96.6862, 51.9332)
  line L1889 (96.6862, 51.9332) -> (96.5149, 52.0205)
  line L1890 (96.5149, 52.0205) -> (96.3594, 52.1335)
  line L1891 (96.3594, 52.1335) -> (96.2235, 52.2694)
  line L1892 (96.2235, 52.2694) -> (96.1105, 52.4249)
  line L1893 (96.1105, 52.4249) -> (96.0232, 52.5962)
  line L1894 (96.0232, 52.5962) -> (95.9638, 52.779)
  line L1895 (95.9638, 52.779) -> (95.9338, 52.9689)
  line L1896 (95.9338, 52.9689) -> (95.93, 53.065)
  line L1897 (95.93, 53.065) -> (95.93, 53.615)
  line L1898 (95.93, 53.615) -> (95.9338, 53.7111)
  line L1899 (95.9338, 53.7111) -> (95.9638, 53.901)
  line L1900 (95.9638, 53.901) -> (96.0232, 54.0838)
  line L1901 (96.0232, 54.0838) -> (96.1105, 54.2551)
  line L1902 (96.1105, 54.2551) -> (96.2235, 54.4106)
  line L1903 (96.2235, 54.4106) -> (96.3594, 54.5465)
  line L1904 (96.3594, 54.5465) -> (96.5149, 54.6595)
  line L1905 (96.5149, 54.6595) -> (96.6862, 54.7468)
  line L1906 (96.6862, 54.7468) -> (96.869, 54.8062)
  line L1907 (96.869, 54.8062) -> (97.0589, 54.8362)
  line L1908 (97.0589, 54.8362) -> (97.2511, 54.8362)
  line L1909 (97.2511, 54.8362) -> (97.441, 54.8062)
  line L1910 (132.366, 54.8062) -> (132.5488, 54.7468)
  line L1911 (132.5488, 54.7468) -> (132.7201, 54.6595)
  line L1912 (132.7201, 54.6595) -> (132.8756, 54.5465)
  line L1913 (132.8756, 54.5465) -> (133.0115, 54.4106)
  line L1914 (133.0115, 54.4106) -> (133.1245, 54.2551)
  line L1915 (133.1245, 54.2551) -> (133.2118, 54.0838)
  line L1916 (133.2118, 54.0838) -> (133.2712, 53.901)
  line L1917 (133.2712, 53.901) -> (133.3012, 53.7111)
  line L1918 (133.3012, 53.7111) -> (133.305, 53.615)
  line L1919 (133.305, 53.615) -> (133.305, 53.065)
  line L1920 (133.305, 53.065) -> (133.3012, 52.9689)
  line L1921 (133.3012, 52.9689) -> (133.2712, 52.779)
  line L1922 (133.2712, 52.779) -> (133.2118, 52.5962)
  line L1923 (133.2118, 52.5962) -> (133.1245, 52.4249)
  line L1924 (133.1245, 52.4249) -> (133.0115, 52.2694)
  line L1925 (133.0115, 52.2694) -> (132.8756, 52.1335)
  line L1926 (132.8756, 52.1335) -> (132.7201, 52.0205)
  line L1927 (132.7201, 52.0205) -> (132.5488, 51.9332)
  line L1928 (132.5488, 51.9332) -> (132.366, 51.8738)
  line L1929 (132.366, 51.8738) -> (132.1761, 51.8438)
  line L1930 (132.1761, 51.8438) -> (131.9839, 51.8438)
  line L1931 (131.9839, 51.8438) -> (131.794, 51.8738)
  line L1932 (131.794, 51.8738) -> (131.6112, 51.9332)
  line L1933 (131.6112, 51.9332) -> (131.4399, 52.0205)
  line L1934 (131.4399, 52.0205) -> (131.2844, 52.1335)
  line L1935 (131.2844, 52.1335) -> (131.1485, 52.2694)
  line L1936 (131.1485, 52.2694) -> (131.0355, 52.4249)
  line L1937 (131.0355, 52.4249) -> (130.9482, 52.5962)
  line L1938 (130.9482, 52.5962) -> (130.8888, 52.779)
  line L1939 (130.8888, 52.779) -> (130.8588, 52.9689)
  line L1940 (130.8588, 52.9689) -> (130.855, 53.065)
  line L1941 (130.855, 53.065) -> (130.855, 53.615)
  line L1942 (130.855, 53.615) -> (130.8588, 53.7111)
  line L1943 (130.8588, 53.7111) -> (130.8888, 53.901)
  line L1944 (130.8888, 53.901) -> (130.9482, 54.0838)
  line L1945 (130.9482, 54.0838) -> (131.0355, 54.2551)
  line L1946 (131.0355, 54.2551) -> (131.1485, 54.4106)
  line L1947 (131.1485, 54.4106) -> (131.2844, 54.5465)
  line L1948 (131.2844, 54.5465) -> (131.4399, 54.6595)
  line L1949 (131.4399, 54.6595) -> (131.6112, 54.7468)
  line L1950 (131.6112, 54.7468) -> (131.794, 54.8062)
  line L1951 (131.794, 54.8062) -> (131.9839, 54.8362)
  line L1952 (131.9839, 54.8362) -> (132.1761, 54.8362)
  line L1953 (132.1761, 54.8362) -> (132.366, 54.8062)
  line L1954 (14.5811, 55.2372) -> (14.6943, 55.1819)
  line L1955 (14.6943, 55.1819) -> (14.7834, 55.0927)
  line L1956 (14.7834, 55.0927) -> (14.8388, 54.9795)
  line L1957 (14.8388, 54.9795) -> (14.8547, 54.8703)
  line L1958 (14.8547, 54.8703) -> (14.8547, 52.6359)
  line L1959 (14.8547, 52.6359) -> (14.8388, 52.5267)
  line L1960 (14.8388, 52.5267) -> (14.7834, 52.4135)
  line L1961 (14.7834, 52.4135) -> (14.6943, 52.3244)
  line L1962 (14.6943, 52.3244) -> (14.5811, 52.269)
  line L1963 (14.5811, 52.269) -> (14.4719, 52.2531)
  line L1964 (14.4719, 52.2531) -> (12.7875, 52.2531)
  line L1965 (12.7875, 52.2531) -> (12.6783, 52.269)
  line L1966 (12.6783, 52.269) -> (12.5651, 52.3244)
  line L1967 (12.5651, 52.3244) -> (12.4759, 52.4135)
  line L1968 (12.4759, 52.4135) -> (12.4206, 52.5267)
  line L1969 (12.4206, 52.5267) -> (12.4047, 52.6359)
  line L1970 (12.4047, 52.6359) -> (12.4047, 54.8703)
  line L1971 (12.4047, 54.8703) -> (12.4206, 54.9795)
  line L1972 (12.4206, 54.9795) -> (12.4759, 55.0927)
  line L1973 (12.4759, 55.0927) -> (12.5651, 55.1819)
  line L1974 (12.5651, 55.1819) -> (12.6783, 55.2372)
  line L1975 (12.6783, 55.2372) -> (12.7875, 55.2531)
  line L1976 (12.7875, 55.2531) -> (14.4719, 55.2531)
  line L1977 (14.4719, 55.2531) -> (14.5811, 55.2372)
  line L1978 (49.5061, 55.2372) -> (49.6193, 55.1819)
  line L1979 (49.6193, 55.1819) -> (49.7084, 55.0927)
  line L1980 (49.7084, 55.0927) -> (49.7638, 54.9795)
  line L1981 (49.7638, 54.9795) -> (49.7797, 54.8703)
  line L1982 (49.7797, 54.8703) -> (49.7797, 52.6359)
  line L1983 (49.7797, 52.6359) -> (49.7638, 52.5267)
  line L1984 (49.7638, 52.5267) -> (49.7084, 52.4135)
  line L1985 (49.7084, 52.4135) -> (49.6193, 52.3244)
  line L1986 (49.6193, 52.3244) -> (49.5061, 52.269)
  line L1987 (49.5061, 52.269) -> (49.3969, 52.2531)
  line L1988 (49.3969, 52.2531) -> (47.7125, 52.2531)
  line L1989 (47.7125, 52.2531) -> (47.6033, 52.269)
  line L1990 (47.6033, 52.269) -> (47.4901, 52.3244)
  line L1991 (47.4901, 52.3244) -> (47.4009, 52.4135)
  line L1992 (47.4009, 52.4135) -> (47.3456, 52.5267)
  line L1993 (47.3456, 52.5267) -> (47.3297, 52.6359)
  line L1994 (47.3297, 52.6359) -> (47.3297, 54.8703)
  line L1995 (47.3297, 54.8703) -> (47.3456, 54.9795)
  line L1996 (47.3456, 54.9795) -> (47.4009, 55.0927)
  line L1997 (47.4009, 55.0927) -> (47.4901, 55.1819)
  line L1998 (47.4901, 55.1819) -> (47.6033, 55.2372)
  line L1999 (47.6033, 55.2372) -> (47.7125, 55.2531)
  line L2000 (47.7125, 55.2531) -> (49.3969, 55.2531)
  line L2001 (49.3969, 55.2531) -> (49.5061, 55.2372)
  line L2002 (84.4311, 55.2372) -> (84.5443, 55.1819)
  line L2003 (84.5443, 55.1819) -> (84.6334, 55.0927)
  line L2004 (84.6334, 55.0927) -> (84.6888, 54.9795)
  line L2005 (84.6888, 54.9795) -> (84.7047, 54.8703)
  line L2006 (84.7047, 54.8703) -> (84.7047, 52.6359)
  line L2007 (84.7047, 52.6359) -> (84.6888, 52.5267)
  line L2008 (84.6888, 52.5267) -> (84.6334, 52.4135)
  line L2009 (84.6334, 52.4135) -> (84.5443, 52.3244)
  line L2010 (84.5443, 52.3244) -> (84.4311, 52.269)
  line L2011 (84.4311, 52.269) -> (84.3219, 52.2531)
  line L2012 (84.3219, 52.2531) -> (82.6375, 52.2531)
  line L2013 (82.6375, 52.2531) -> (82.5283, 52.269)
  line L2014 (82.5283, 52.269) -> (82.4151, 52.3244)
  line L2015 (82.4151, 52.3244) -> (82.3259, 52.4135)
  line L2016 (82.3259, 52.4135) -> (82.2706, 52.5267)
  line L2017 (82.2706, 52.5267) -> (82.2547, 52.6359)
  line L2018 (82.2547, 52.6359) -> (82.2547, 54.8703)
  line L2019 (82.2547, 54.8703) -> (82.2706, 54.9795)
  line L2020 (82.2706, 54.9795) -> (82.3259, 55.0927)
  line L2021 (82.3259, 55.0927) -> (82.4151, 55.1819)
  line L2022 (82.4151, 55.1819) -> (82.5283, 55.2372)
  line L2023 (82.5283, 55.2372) -> (82.6375, 55.2531)
  line L2024 (82.6375, 55.2531) -> (84.3219, 55.2531)
  line L2025 (84.3219, 55.2531) -> (84.4311, 55.2372)
  line L2026 (119.3561, 55.2372) -> (119.4693, 55.1819)
  line L2027 (119.4693, 55.1819) -> (119.5584, 55.0927)
  line L2028 (119.5584, 55.0927) -> (119.6138, 54.9795)
  line L2029 (119.6138, 54.9795) -> (119.6297, 54.8703)
  line L2030 (119.6297, 54.8703) -> (119.6297, 52.6359)
  line L2031 (119.6297, 52.6359) -> (119.6138, 52.5267)
  line L2032 (119.6138, 52.5267) -> (119.5584, 52.4135)
  line L2033 (119.5584, 52.4135) -> (119.4693, 52.3244)
  line L2034 (119.4693, 52.3244) -> (119.3561, 52.269)
  line L2035 (119.3561, 52.269) -> (119.2469, 52.2531)
  line L2036 (119.2469, 52.2531) -> (117.5625, 52.2531)
  line L2037 (117.5625, 52.2531) -> (117.4533, 52.269)
  line L2038 (117.4533, 52.269) -> (117.3401, 52.3244)
  line L2039 (117.3401, 52.3244) -> (117.2509, 52.4135)
  line L2040 (117.2509, 52.4135) -> (117.1956, 52.5267)
  line L2041 (117.1956, 52.5267) -> (117.1797, 52.6359)
  line L2042 (117.1797, 52.6359) -> (117.1797, 54.8703)
  line L2043 (117.1797, 54.8703) -> (117.1956, 54.9795)
  line L2044 (117.1956, 54.9795) -> (117.2509, 55.0927)
  line L2045 (117.2509, 55.0927) -> (117.3401, 55.1819)
  line L2046 (117.3401, 55.1819) -> (117.4533, 55.2372)
  line L2047 (117.4533, 55.2372) -> (117.5625, 55.2531)
  line L2048 (117.5625, 55.2531) -> (119.2469, 55.2531)
  line L2049 (119.2469, 55.2531) -> (119.3561, 55.2372)
  line L2050 (16.4157, 55.2193) -> (16.5985, 55.1599)
  line L2051 (16.5985, 55.1599) -> (16.7697, 55.0726)
  line L2052 (16.7697, 55.0726) -> (16.9253, 54.9596)
  line L2053 (16.9253, 54.9596) -> (17.0612, 54.8237)
  line L2054 (17.0612, 54.8237) -> (17.1742, 54.6682)
  line L2055 (17.1742, 54.6682) -> (17.2614, 54.4969)
  line L2056 (17.2614, 54.4969) -> (17.3208, 54.3141)
  line L2057 (17.3208, 54.3141) -> (17.3509, 54.1242)
  line L2058 (17.3509, 54.1242) -> (17.3547, 54.0281)
  line L2059 (17.3547, 54.0281) -> (17.3547, 53.4781)
  line L2060 (17.3547, 53.4781) -> (17.3509, 53.382)
  line L2061 (17.3509, 53.382) -> (17.3208, 53.1921)
  line L2062 (17.3208, 53.1921) -> (17.2614, 53.0093)
  line L2063 (17.2614, 53.0093) -> (17.1742, 52.8381)
  line L2064 (17.1742, 52.8381) -> (17.0612, 52.6825)
  line L2065 (17.0612, 52.6825) -> (16.9253, 52.5466)
  line L2066 (16.9253, 52.5466) -> (16.7697, 52.4336)
  line L2067 (16.7697, 52.4336) -> (16.5985, 52.3464)
  line L2068 (16.5985, 52.3464) -> (16.4157, 52.287)
  line L2069 (16.4157, 52.287) -> (16.2258, 52.2569)
  line L2070 (16.2258, 52.2569) -> (16.0336, 52.2569)
  line L2071 (16.0336, 52.2569) -> (15.8437, 52.287)
  line L2072 (15.8437, 52.287) -> (15.6609, 52.3464)
  line L2073 (15.6609, 52.3464) -> (15.4896, 52.4336)
  line L2074 (15.4896, 52.4336) -> (15.3341, 52.5466)
  line L2075 (15.3341, 52.5466) -> (15.1982, 52.6825)
  line L2076 (15.1982, 52.6825) -> (15.0852, 52.8381)
  line L2077 (15.0852, 52.8381) -> (14.9979, 53.0093)
  line L2078 (14.9979, 53.0093) -> (14.9385, 53.1921)
  line L2079 (14.9385, 53.1921) -> (14.9085, 53.382)
  line L2080 (14.9085, 53.382) -> (14.9047, 53.4781)
  line L2081 (14.9047, 53.4781) -> (14.9047, 54.0281)
  line L2082 (14.9047, 54.0281) -> (14.9085, 54.1242)
  line L2083 (14.9085, 54.1242) -> (14.9385, 54.3141)
  line L2084 (14.9385, 54.3141) -> (14.9979, 54.4969)
  line L2085 (14.9979, 54.4969) -> (15.0852, 54.6682)
  line L2086 (15.0852, 54.6682) -> (15.1982, 54.8237)
  line L2087 (15.1982, 54.8237) -> (15.3341, 54.9596)
  line L2088 (15.3341, 54.9596) -> (15.4896, 55.0726)
  line L2089 (15.4896, 55.0726) -> (15.6609, 55.1599)
  line L2090 (15.6609, 55.1599) -> (15.8437, 55.2193)
  line L2091 (15.8437, 55.2193) -> (16.0336, 55.2493)
  line L2092 (16.0336, 55.2493) -> (16.2258, 55.2493)
  line L2093 (16.2258, 55.2493) -> (16.4157, 55.2193)
  line L2094 (51.3407, 55.2193) -> (51.5235, 55.1599)
  line L2095 (51.5235, 55.1599) -> (51.6947, 55.0726)
  line L2096 (51.6947, 55.0726) -> (51.8503, 54.9596)
  line L2097 (51.8503, 54.9596) -> (51.9862, 54.8237)
  line L2098 (51.9862, 54.8237) -> (52.0992, 54.6682)
  line L2099 (52.0992, 54.6682) -> (52.1864, 54.4969)
  line L2100 (52.1864, 54.4969) -> (52.2458, 54.3141)
  line L2101 (52.2458, 54.3141) -> (52.2759, 54.1242)
  line L2102 (52.2759, 54.1242) -> (52.2797, 54.0281)
  line L2103 (52.2797, 54.0281) -> (52.2797, 53.4781)
  line L2104 (52.2797, 53.4781) -> (52.2759, 53.382)
  line L2105 (52.2759, 53.382) -> (52.2458, 53.1921)
  line L2106 (52.2458, 53.1921) -> (52.1864, 53.0093)
  line L2107 (52.1864, 53.0093) -> (52.0992, 52.8381)
  line L2108 (52.0992, 52.8381) -> (51.9862, 52.6825)
  line L2109 (51.9862, 52.6825) -> (51.8503, 52.5466)
  line L2110 (51.8503, 52.5466) -> (51.6947, 52.4336)
  line L2111 (51.6947, 52.4336) -> (51.5235, 52.3464)
  line L2112 (51.5235, 52.3464) -> (51.3407, 52.287)
  line L2113 (51.3407, 52.287) -> (51.1508, 52.2569)
  line L2114 (51.1508, 52.2569) -> (50.9586, 52.2569)
  line L2115 (50.9586, 52.2569) -> (50.7687, 52.287)
  line L2116 (50.7687, 52.287) -> (50.5859, 52.3464)
  line L2117 (50.5859, 52.3464) -> (50.4146, 52.4336)
  line L2118 (50.4146, 52.4336) -> (50.2591, 52.5466)
  line L2119 (50.2591, 52.5466) -> (50.1232, 52.6825)
  line L2120 (50.1232, 52.6825) -> (50.0102, 52.8381)
  line L2121 (50.0102, 52.8381) -> (49.9229, 53.0093)
  line L2122 (49.9229, 53.0093) -> (49.8635, 53.1921)
  line L2123 (49.8635, 53.1921) -> (49.8335, 53.382)
  line L2124 (49.8335, 53.382) -> (49.8297, 53.4781)
  line L2125 (49.8297, 53.4781) -> (49.8297, 54.0281)
  line L2126 (49.8297, 54.0281) -> (49.8335, 54.1242)
  line L2127 (49.8335, 54.1242) -> (49.8635, 54.3141)
  line L2128 (49.8635, 54.3141) -> (49.9229, 54.4969)
  line L2129 (49.9229, 54.4969) -> (50.0102, 54.6682)
  line L2130 (50.0102, 54.6682) -> (50.1232, 54.8237)
  line L2131 (50.1232, 54.8237) -> (50.2591, 54.9596)
  line L2132 (50.2591, 54.9596) -> (50.4146, 55.0726)
  line L2133 (50.4146, 55.0726) -> (50.5859, 55.1599)
  line L2134 (50.5859, 55.1599) -> (50.7687, 55.2193)
  line L2135 (50.7687, 55.2193) -> (50.9586, 55.2493)
  line L2136 (50.9586, 55.2493) -> (51.1508, 55.2493)
  line L2137 (51.1508, 55.2493) -> (51.3407, 55.2193)
  line L2138 (86.2657, 55.2193) -> (86.4485, 55.1599)
  line L2139 (86.4485, 55.1599) -> (86.6197, 55.0726)
  line L2140 (86.6197, 55.0726) -> (86.7753, 54.9596)
  line L2141 (86.7753, 54.9596) -> (86.9112, 54.8237)
  line L2142 (86.9112, 54.8237) -> (87.0242, 54.6682)
  line L2143 (87.0242, 54.6682) -> (87.1114, 54.4969)
  line L2144 (87.1114, 54.4969) -> (87.1708, 54.3141)
  line L2145 (87.1708, 54.3141) -> (87.2009, 54.1242)
  line L2146 (87.2009, 54.1242) -> (87.2047, 54.0281)
  line L2147 (87.2047, 54.0281) -> (87.2047, 53.4781)
  line L2148 (87.2047, 53.4781) -> (87.2009, 53.382)
  line L2149 (87.2009, 53.382) -> (87.1708, 53.1921)
  line L2150 (87.1708, 53.1921) -> (87.1114, 53.0093)
  line L2151 (87.1114, 53.0093) -> (87.0242, 52.8381)
  line L2152 (87.0242, 52.8381) -> (86.9112, 52.6825)
  line L2153 (86.9112, 52.6825) -> (86.7753, 52.5466)
  line L2154 (86.7753, 52.5466) -> (86.6197, 52.4336)
  line L2155 (86.6197, 52.4336) -> (86.4485, 52.3464)
  line L2156 (86.4485, 52.3464) -> (86.2657, 52.287)
  line L2157 (86.2657, 52.287) -> (86.0758, 52.2569)
  line L2158 (86.0758, 52.2569) -> (85.8836, 52.2569)
  line L2159 (85.8836, 52.2569) -> (85.6937, 52.287)
  line L2160 (85.6937, 52.287) -> (85.5109, 52.3464)
  line L2161 (85.5109, 52.3464) -> (85.3396, 52.4336)
  line L2162 (85.3396, 52.4336) -> (85.1841, 52.5466)
  line L2163 (85.1841, 52.5466) -> (85.0482, 52.6825)
  line L2164 (85.0482, 52.6825) -> (84.9352, 52.8381)
  line L2165 (84.9352, 52.8381) -> (84.8479, 53.0093)
  line L2166 (84.8479, 53.0093) -> (84.7885, 53.1921)
  line L2167 (84.7885, 53.1921) -> (84.7585, 53.382)
  line L2168 (84.7585, 53.382) -> (84.7547, 53.4781)
  line L2169 (84.7547, 53.4781) -> (84.7547, 54.0281)
  line L2170 (84.7547, 54.0281) -> (84.7585, 54.1242)
  line L2171 (84.7585, 54.1242) -> (84.7885, 54.3141)
  line L2172 (84.7885, 54.3141) -> (84.8479, 54.4969)
  line L2173 (84.8479, 54.4969) -> (84.9352, 54.6682)
  line L2174 (84.9352, 54.6682) -> (85.0482, 54.8237)
  line L2175 (85.0482, 54.8237) -> (85.1841, 54.9596)
  line L2176 (85.1841, 54.9596) -> (85.3396, 55.0726)
  line L2177 (85.3396, 55.0726) -> (85.5109, 55.1599)
  line L2178 (85.5109, 55.1599) -> (85.6937, 55.2193)
  line L2179 (85.6937, 55.2193) -> (85.8836, 55.2493)
  line L2180 (85.8836, 55.2493) -> (86.0758, 55.2493)
  line L2181 (86.0758, 55.2493) -> (86.2657, 55.2193)
  line L2182 (121.1907, 55.2193) -> (121.3735, 55.1599)
  line L2183 (121.3735, 55.1599) -> (121.5447, 55.0726)